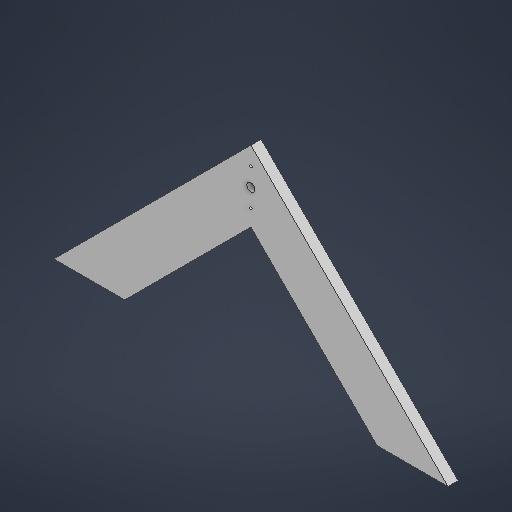
# Autodesk Inventor part: base
Saved by Autodesk Inventor 2026.1 (Build 301233000, 233)
## iProperties
Created: 2025-11-10
Part Number: base
Material: Generic
Document SubType Name: Modeling
Designer: shiva
Density: 1 g/cm^3
Appearance: Default
Author: shiva
Autodesk Inventor part; units mm, degrees
ref_plane "YZ Plane" through (0, 0, 0) normal (1, 0, 0) x (0, 1, 0)
ref_plane "XZ Plane" through (0, 0, 0) normal (0, 1, 0) x (-1, 0, 0)
ref_plane "XY Plane" through (0, 0, 0) normal (0, 0, 1) x (1, 0, 0)
sketch "Sketch1" plane through (0, 0, 0) normal (0, 0, 1) x (1, 0, 0)
  circle A0 centre (0, 400) radius 10
  line L0 (-70.4278, 420.4278) -> (-19.6278, 420.4278) construction
  line L1 (-17.9605, 332.0395) -> (32.8395, 332.0395) construction
  line L2 (-88.3883, 402.4673) -> (314.079, 0)
  line L3 (0, 490.8557) -> (490.8557, 0)
  line L4 (88.3883, 402.4673) -> (-314.079, 0)
  line L5 (0, 490.8557) -> (-490.8557, 0)
  line L6 (-490.8557, 0) -> (-314.079, 0)
  line L7 (-333.0616, 0) -> (-314.079, 0) construction
  line L8 (0, 0) -> (357.2929, 0) construction
  line L9 (-490.8557, 0) -> (-314.079, 0)
  line L10 (314.079, 0) -> (490.8557, 0)
  line L11 (0, 390) -> (0, 400)
  line L12 (17.9605, 332.0395) -> (-70.4278, 420.4278)
  line L13 (-17.9605, 332.0395) -> (70.4278, 420.4278)
  line L14 (0, 445) -> (0, 355)
  circle A1 centre (0, 355) radius 3
  circle A2 centre (0, 445) radius 3
  point P0 (0, 314.079)
  dimension "d1" = 20
  dimension "d0" = 400
  dimension "d18" = 125
  dimension "d28" = 125
  dimension "d29" = 90
  dimension "d30" = 6
  dimension "d31" = 6
  constraints: 30 end point, 10 point on line, 9 horizontal, 2 centre point, 2 coincident, 2 parallel, 2 vertical, 1 midpoint, 1 perpendicular, 1 vertical alignment, 4 other
  measures "d0" distance of L11.end L8.start
  measures "d18" distance between parallel lines of L4 L5
  measures "d28" distance between parallel lines of L3 L2
  measures "d29" distance of L14.start L14.end
  measures "d30" diameter of A1
  measures "d31" diameter of A2
extrude "Extrusion1" add sketch "Sketch1" along normal blind 25.4
body "Solid1"
